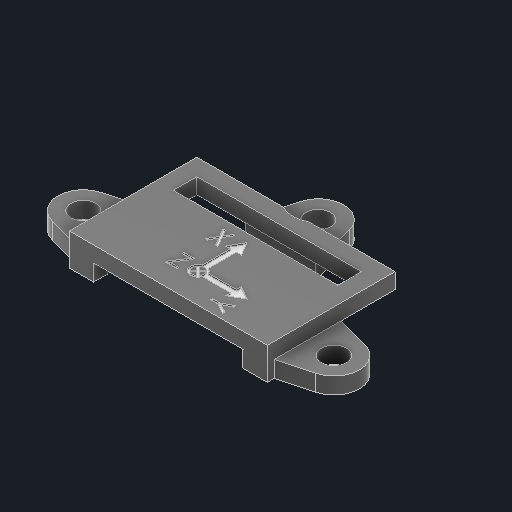
# Autodesk Inventor part: Capa IMU tampa
Saved by Autodesk Inventor 2026.1 (Build 301233000, 233)
## iProperties
Created: 2025-03-19
Part Number: Capa IMU tampa
Material: Genérico
Document SubType Name: Modeling
Designer: Cliente
Density: 1 g/cm^3
Appearance: Padrão
Mass: 3.26729 g
Surface Area: 39.0729 cm^2
Volume: 3.26729 cm^3
Author: Cliente
Autodesk Inventor part; units mm, degrees
ref_plane "YZ Plane" through (0, 0, 0) normal (1, 0, 0) x (0, 1, 0)
ref_plane "XZ Plane" through (0, 0, 0) normal (0, 1, 0) x (-1, 0, 0)
ref_plane "XY Plane" through (0, 0, 0) normal (0, 0, 1) x (1, 0, 0)
sketch "Esboço1" plane through (0, 0, 0) normal (0, 1, 0) x (-1, 0, 0)
  line L0 (-10.5, 6) -> (10.5, 6)
  line L1 (10.5, 6) -> (10.5, -6)
  line L2 (10.5, -6) -> (-10.5, -6)
  line L3 (-10.5, -6) -> (-10.5, 6)
  line L4 (-10.5, 6) -> (10.5, -6) construction
  line L5 (10.5, 6) -> (-10.5, -6) construction
  line L6 (-10.65, -6.15) -> (10.65, -6.15)
  line L7 (10.65, -6.15) -> (10.65, 6.15)
  line L8 (10.65, 6.15) -> (-10.65, 6.15)
  line L9 (-10.65, 6.15) -> (-10.65, -6.15)
  line L10 (12.65, -8.15) -> (-12.65, -8.15)
  line L11 (-12.65, -8.15) -> (-12.65, 8.15)
  line L12 (-12.65, 8.15) -> (12.65, 8.15)
  line L13 (12.65, 8.15) -> (12.65, -8.15)
  circle A0 centre (16, 3) radius 1.6
  circle A1 centre (-16, 3) radius 1.6
  circle A2 centre (0, -11) radius 1.6
  circle A3 centre (0, -11) radius 4 construction
  circle A4 centre (-12.65, -8.15) radius 4 construction
  circle A5 centre (-16, 3) radius 4 construction
  circle A6 centre (-12.65, 8.15) radius 4 construction
  circle A7 centre (12.65, 8.15) radius 4 construction
  circle A8 centre (16, 3) radius 4 construction
  circle A9 centre (12.65, -8.15) radius 4 construction
  line L14 (13.5291, -12.0522) -> (0.8791, -14.9022)
  line L15 (-0.8791, -14.9022) -> (-13.5291, -12.0522)
  line L16 (19.8308, 1.849) -> (16.4808, -9.301)
  line L17 (-16.4808, -9.301) -> (-19.8308, 1.849)
  line L18 (19.353, 5.1811) -> (16.003, 10.3311)
  line L19 (-16.003, 10.3311) -> (-19.353, 5.1811)
  line L20 (12.65, 12.15) -> (-12.65, 12.15)
  arc A10 (13.5291, -12.0522) -> (16.4808, -9.301) centre (12.65, -8.15) ccw
  arc A11 (-0.8791, -14.9022) -> (0.8791, -14.9022) centre (0, -11) ccw
  arc A12 (-16.4808, -9.301) -> (-13.5291, -12.0522) centre (-12.65, -8.15) ccw
  arc A13 (19.8308, 1.849) -> (19.353, 5.1811) centre (16, 3) ccw
  arc A14 (16.003, 10.3311) -> (12.65, 12.15) centre (12.65, 8.15) ccw
  arc A15 (-12.65, 12.15) -> (-16.003, 10.3311) centre (-12.65, 8.15) ccw
  arc A16 (-19.353, 5.1811) -> (-19.8308, 1.849) centre (-16, 3) ccw
  line L21 (10.65, 6.15) -> (5.65, 6.15)
  line L22 (5.65, 6.15) -> (5.65, 3.15)
  line L23 (5.65, 3.15) -> (10.65, 3.15)
  line L24 (10.65, 3.15) -> (10.65, 6.15)
  line L25 (-10.65, 6.15) -> (-8.15, 6.15)
  line L26 (-8.15, 6.15) -> (-8.15, -3.85)
  line L27 (-8.15, -3.85) -> (-10.65, -3.85)
  line L28 (-10.65, -3.85) -> (-10.65, 6.15)
  circle A17 centre (16, 3) radius 3.25
  circle A18 centre (0, -11) radius 3.25
  circle A19 centre (-16, 3) radius 3.25
  line L29 (-16.8412, -0.1393) -> (-12.65, -1.2623)
  line L30 (-16.8412, -0.1393) -> (-12.5022, -0.1393) construction
  line L31 (-16.8412, 6.1393) -> (-12.65, 7.2623)
  line L32 (-16.8412, 6.1393) -> (-12.5022, 6.1393) construction
  line L33 (16.8412, 6.1393) -> (12.65, 7.2623)
  line L34 (16.8412, 6.1393) -> (21.1802, 6.1393) construction
  line L35 (16.8412, -0.1393) -> (12.65, -1.2623)
  line L36 (16.8412, -0.1393) -> (21.1802, -0.1393) construction
  line L37 (-3.1393, -11.8412) -> (-4.1283, -8.15)
  line L38 (-3.1393, -11.8412) -> (0.6821, -11.8412) construction
  line L39 (3.1393, -11.8412) -> (4.1283, -8.15)
  line L40 (3.1393, -11.8412) -> (6.9606, -11.8412) construction
  point P0 (0, 0)
  dimension "d0" = 21
  dimension "d1" = 12
  dimension "d2" = 0.15
  dimension "d3" = 2
  dimension "d4" = 3.2
  dimension "d5" = 3.2
  dimension "d6" = 3.2
  dimension "d7" = 11
  dimension "d8" = 3
  dimension "d9" = 16
  dimension "d10" = 16
  dimension "d11" = 8
  dimension "d12" = 8
  dimension "d13" = 8
  dimension "d14" = 8
  dimension "d15" = 8
  dimension "d16" = 8
  dimension "d17" = 8
  dimension "d22" = 5
  dimension "d23" = 3
  dimension "d24" = 2.5
  dimension "d25" = 10
  dimension "d28" = 6.5
  dimension "d29" = 6.5
  dimension "d33" = 6.5
  dimension "d34" = 15
  dimension "d35" = 15
  dimension "d36" = 165
  dimension "d37" = 165
  dimension "d38" = 105
  dimension "d39" = 75
  constraints: 82 end point, 34 point on circle, 20 centre point, 19 tangent, 17 coincident, 10 horizontal, 10 parallel, 6 equal length, 6 point on line, 5 perpendicular, 2 midpoint, 1 horizontal alignment, 1 vertical alignment, 6 other
  measures "d0" distance of L1.end L2.end
  measures "d1" distance of L0.end L1.end
  measures "d2" distance between parallel lines of L2 L6
  measures "d3" distance between parallel lines of L6 L10
  measures "d4" diameter of A0
  measures "d5" diameter of A1
  measures "d6" diameter of A2
  measures "d7" distance of point (0, 0) A2.centre
  measures "d8" vertical distance of A1.centre point (0, 0)
  measures "d9" horizontal distance of point (0, 0) A1.centre
  measures "d10" horizontal distance of A0.centre point (0, 0)
  measures "d11" diameter of A3
  measures "d12" diameter of A4
  measures "d13" diameter of A5
  measures "d14" diameter of A6
  measures "d15" diameter of A7
  measures "d16" diameter of A8
  measures "d17" diameter of A9
  measures "d22" distance of L23.end L22.end
  measures "d23" distance of L22.end L21.end
  measures "d24" distance of L26.end L27.end
  measures "d25" distance of L25.end L26.end
  measures "d28" diameter of A17
  measures "d29" diameter of A18
  measures "d33" diameter of A19
  measures "d34" angle of L29 L30
  measures "d35" angle of L32 L31
  measures "d36" angle of L34 L33
  measures "d37" angle of L35 L36
  measures "d38" angle of L38 L37
  measures "d39" angle of L40 L39
extrude "Extrusão1" add sketch "Esboço1" against normal blind 2 contours L3 L27 L9 L8 L26 L0 | L0 L26 L27 L3 | L26 L8 L22 L0 | L0 L22 L23 L1 L2 L3 L27 L26 | L3 L2 L1 L23 L7 L6 L9 L27 | L22 L8 L7 L23 L1 L0 | L0 L1 L23 L22 | L10 A18 L11 L12 L13 | L39 A18 L10 | L13 L33 A17 L35 | A18 L10 | L10 A18 | A17 | A18 L37 L10 | L11 L29 A19 L31 | A19 | L14 A11 L15 A12 L17 A16 L19 A15 L20 A14 L18 A13 L16 A10
extrude "Extrusão2" add sketch "Esboço1" along normal blind 3.1 contours L10 A18 L11 L12 L13 | L39 A18 L10 | L13 L33 A17 L35 | A18 L10 | L10 A18 | A17 | A18 L37 L10 | L11 L29 A19 L31 | A19
extrude "Extrusão3" add sketch "Esboço1" along normal blind 1.4 contours L3 L27 L9 L8 L26 L0 | L0 L26 L27 L3 | L22 L8 L7 L23 L1 L0 | L0 L1 L23 L22
sketch "Esboço3" plane through (0, 3.1, 0) normal (0, 1, 0) x (1, 0, 0)
  line L0 (-12.65, -8.15) -> (12.65, -8.15) projected
  line L1 (12.65, -8.15) -> (12.65, -7.2623) projected
  line L2 (12.65, -7.2623) -> (16.8412, -6.1393) projected
  arc A0 (16.8412, -6.1393) -> (16.8412, 0.1393) centre (16, -3) ccw projected
  line L3 (16.8412, 0.1393) -> (12.65, 1.2623) projected
  line L4 (12.65, 1.2623) -> (12.65, 8.15) projected
  line L5 (12.65, 8.15) -> (4.1283, 8.15) projected
  line L6 (4.1283, 8.15) -> (3.1393, 11.8412) projected
  arc A1 (3.1393, 11.8412) -> (-3.1393, 11.8412) centre (0, 11) ccw projected
  line L7 (-3.1393, 11.8412) -> (-4.1283, 8.15) projected
  line L8 (-4.1283, 8.15) -> (-12.65, 8.15) projected
  line L9 (-12.65, 8.15) -> (-12.65, 1.2623) projected
  line L10 (-12.65, 1.2623) -> (-16.8412, 0.1393) projected
  arc A2 (-16.8412, 0.1393) -> (-16.8412, -6.1393) centre (-16, -3) ccw projected
  line L11 (-16.8412, -6.1393) -> (-12.65, -7.2623) projected
  line L12 (-12.65, -7.2623) -> (-12.65, -8.15) projected
  line L13 (10.65, 6.15) -> (10.65, -6.15) projected
  line L14 (10.65, -6.15) -> (-10.65, -6.15) projected
  line L15 (-10.65, -6.15) -> (-10.65, 6.15) projected
  line L16 (-10.65, 6.15) -> (10.65, 6.15) projected
  circle A3 centre (-16, -3) radius 1.6 projected
  circle A4 centre (0, 11) radius 1.6 projected
  circle A5 centre (16, -3) radius 1.6 projected
  line L17 (-12.65, 1.2623) -> (-10.65, 1.7982)
  line L18 (-12.65, -7.2623) -> (-9.337, -8.15)
  line L19 (12.65, -8.15) -> (-12.65, -8.15) projected
  line L20 (-12.65, 1.2623) -> (-16.8412, 0.1393) projected
  line L21 (-16.8412, -6.1393) -> (-12.65, -7.2623) projected
  line L22 (-9.337, -8.15) -> (-9.337, -6.15)
  line L23 (-4.1283, 8.15) -> (-4.6642, 6.15)
  line L24 (10.65, 6.15) -> (-10.65, 6.15) projected
  line L25 (4.1283, 8.15) -> (4.6642, 6.15)
  line L26 (0, 0) -> (0, 2.6223)
  line L27 (4.1283, 8.15) -> (3.1393, 11.8412) projected
  line L28 (-3.1393, 11.8412) -> (-4.1283, 8.15) projected
  line L29 (12.65, 1.2623) -> (10.65, 1.7982)
  line L30 (12.65, -7.2623) -> (9.337, -8.15)
  line L31 (9.337, -8.15) -> (9.337, -6.15)
  constraints: 18 end point, 5 point on line, 4 collinear, 3 symmetric about line, 1 perpendicular, 1 vertical
extrude "Extrusão4" cut sketch "Esboço3" against normal blind 2.1 contours L12 L18 L0 | L18 L11 A2 L10 L17 L15 L14 L22 | L30 L1 L0 | L31 L14 L13 L29 L3 A0 L2 L30 | L23 L7 A1 L6 L25 L16
sketch "Esboço4" plane through (0, 1, 0) normal (0, 1, 0) x (1, 0, 0)
  line L0 (-4.6642, 6.15) -> (-4.1283, 8.15) projected
  line L1 (4.6642, 6.15) -> (-4.6642, 6.15) projected
  line L2 (4.1283, 8.15) -> (4.6642, 6.15) projected
  line L3 (3.1393, 11.8412) -> (4.1283, 8.15) projected
  arc A0 (3.1393, 11.8412) -> (-3.1393, 11.8412) centre (0, 11) ccw projected
  line L4 (-4.1283, 8.15) -> (-3.1393, 11.8412) projected
  circle A1 centre (0, 11) radius 1.6 projected
  line L5 (-12.65, -7.2623) -> (-16.8412, -6.1393) projected
  line L6 (-12.65, -8.15) -> (-12.65, -7.2623) projected
  line L7 (-9.337, -8.15) -> (-12.65, -8.15) projected
  line L8 (-9.337, -6.15) -> (-9.337, -8.15) projected
  line L9 (-10.65, -6.15) -> (-9.337, -6.15) projected
  line L10 (-10.65, -3.15) -> (-10.65, -6.15) projected
  line L11 (-10.65, 1.7982) -> (-10.65, -3.15) projected
  line L12 (-12.65, 1.2623) -> (-10.65, 1.7982) projected
  line L13 (-16.8412, 0.1393) -> (-12.65, 1.2623) projected
  arc A2 (-16.8412, 0.1393) -> (-16.8412, -6.1393) centre (-16, -3) ccw projected
  circle A3 centre (-16, -3) radius 1.6 projected
  line L14 (10.65, 1.7982) -> (12.65, 1.2623) projected
  line L15 (10.65, -6.15) -> (10.65, 1.7982) projected
  line L16 (9.337, -6.15) -> (10.65, -6.15) projected
  line L17 (9.337, -8.15) -> (9.337, -6.15) projected
  line L18 (12.65, -8.15) -> (9.337, -8.15) projected
  line L19 (12.65, -7.2623) -> (12.65, -8.15) projected
  line L20 (16.8412, -6.1393) -> (12.65, -7.2623) projected
  arc A4 (16.8412, -6.1393) -> (16.8412, 0.1393) centre (16, -3) ccw projected
  line L21 (12.65, 1.2623) -> (16.8412, 0.1393) projected
  circle A5 centre (16, -3) radius 1.6 projected
  point P0 (0, 0)
extrude "Extrusão5" add sketch "Esboço4" along normal blind 2.1 separate body
sketch "Esboço5" plane through (0, 3.1, 0) normal (0, 1, 0) x (1, 0, 0)
  line L0 (-4.6642, 6.15) -> (-4.1283, 8.15) projected
  line L1 (-4.1283, 8.15) -> (-12.65, 8.15) projected
  line L2 (-12.65, 8.15) -> (-12.65, 1.2623) projected
  line L3 (-12.65, 1.2623) -> (-10.65, 1.7982) projected
  line L4 (-10.65, 1.7982) -> (-10.65, 6.15) projected
  line L5 (-10.65, 6.15) -> (-4.6642, 6.15) projected
  line L6 (10.65, 1.7982) -> (12.65, 1.2623) projected
  line L7 (12.65, 1.2623) -> (12.65, 8.15) projected
  line L8 (12.65, 8.15) -> (4.1283, 8.15) projected
  line L9 (4.1283, 8.15) -> (4.6642, 6.15) projected
  line L10 (4.6642, 6.15) -> (10.65, 6.15) projected
  line L11 (10.65, 6.15) -> (10.65, 1.7982) projected
  line L12 (9.337, -8.15) -> (9.337, -6.15) projected
  line L13 (9.337, -6.15) -> (-9.337, -6.15) projected
  line L14 (-9.337, -6.15) -> (-9.337, -8.15) projected
  line L15 (-9.337, -8.15) -> (9.337, -8.15) projected
  line L16 (8.15, -6.15) -> (8.15, 3.85) projected
  line L17 (8.15, 3.85) -> (10.65, 3.85) projected
  line L18 (10.65, 3.85) -> (10.65, 6.15) projected
  line L19 (10.65, 6.15) -> (-10.65, 6.15) projected
  line L20 (-10.65, 6.15) -> (-10.65, -3.15) projected
  line L21 (-10.65, -3.15) -> (-5.65, -3.15) projected
  line L22 (-5.65, -3.15) -> (-5.65, -6.15) projected
  line L23 (-5.65, -6.15) -> (8.15, -6.15) projected
  line L24 (-10.65, -6.15) -> (-10.65, -3.15) projected
  line L25 (-9.337, -6.15) -> (-10.65, -6.15) projected
  line L26 (-5.65, -6.15) -> (-9.337, -6.15) projected
  line L27 (-5.65, -6.15) -> (-5.65, -3.15) projected
  line L28 (-5.65, -3.15) -> (-10.65, -3.15) projected
  line L29 (8.15, 3.85) -> (8.15, -6.15) projected
  line L30 (9.337, -6.15) -> (8.15, -6.15) projected
  line L31 (10.65, -6.15) -> (9.337, -6.15) projected
  line L32 (10.65, 1.7982) -> (10.65, -6.15) projected
  line L33 (10.65, 3.85) -> (10.65, 1.7982) projected
  line L34 (10.65, 3.85) -> (8.15, 3.85) projected
  line L35 (10.5, 3) -> (-10.5, 3)
  line L36 (-10.5, 3) -> (-10.5, 6)
  line L37 (-10.5, 6) -> (10.5, 6)
  line L38 (10.5, 6) -> (10.5, 3)
  line L39 (10.5, 3) -> (-10.5, 6) construction
  line L40 (-10.5, 3) -> (10.5, 6) construction
  line L41 (-16.8412, -6.1393) -> (-12.65, -7.2623) projected
  line L42 (-12.65, -7.2623) -> (-12.65, -8.15) projected
  line L43 (-12.65, -8.15) -> (-9.337, -8.15) projected
  line L44 (-9.337, -8.15) -> (-9.337, -6.15) projected
  line L45 (-9.337, -6.15) -> (-10.65, -6.15) projected
  line L46 (-10.65, -6.15) -> (-10.65, 1.7982) projected
  line L47 (-10.65, 1.7982) -> (-16.8412, 0.1393) projected
  arc A0 (-16.8412, 0.1393) -> (-16.8412, -6.1393) centre (-16, -3) ccw projected
  circle A1 centre (-16, -3) radius 1.6 projected
  line L48 (16.8412, 0.1393) -> (10.65, 1.7982) projected
  line L49 (10.65, 1.7982) -> (10.65, -6.15) projected
  line L50 (10.65, -6.15) -> (9.337, -6.15) projected
  line L51 (9.337, -6.15) -> (9.337, -8.15) projected
  line L52 (9.337, -8.15) -> (12.65, -8.15) projected
  line L53 (12.65, -8.15) -> (12.65, -7.2623) projected
  line L54 (12.65, -7.2623) -> (16.8412, -6.1393) projected
  arc A2 (16.8412, -6.1393) -> (16.8412, 0.1393) centre (16, -3) ccw projected
  circle A3 centre (16, -3) radius 1.6 projected
  line L55 (-3.1393, 11.8412) -> (-4.6642, 6.15) projected
  line L56 (-4.6642, 6.15) -> (4.6642, 6.15) projected
  line L57 (4.6642, 6.15) -> (3.1393, 11.8412) projected
  arc A4 (3.1393, 11.8412) -> (-3.1393, 11.8412) centre (0, 11) ccw projected
  circle A5 centre (0, 11) radius 1.6 projected
  circle A6 centre (-16, -3) radius 3.25
  circle A7 centre (16, -3) radius 3.25
  circle A8 centre (0, 11) radius 3.25
  line L58 (-4.1283, 8.15) -> (4.1283, 8.15)
  line L59 (-12.65, 1.2623) -> (-12.65, -7.2623)
  line L60 (12.65, 1.2623) -> (12.65, -7.2623)
  point P0 (0, 0)
  point P1 (0, 4.5)
  point P2 (-1.562, 8.15)
  point P3 (1.562, 8.15)
  dimension "d46" = 21
  dimension "d47" = 3
  dimension "d48" = 0.15
  dimension "d49" = 6.5
  dimension "d50" = 6.5
  dimension "d51" = 6.5
  constraints: 18 end point, 3 centre point, 3 coincident, 3 parallel, 2 horizontal, 2 midpoint, 2 perpendicular, 1 vertical alignment
  measures "d46" distance of L36.end L37.end
  measures "d47" distance of L35.end L36.end
  measures "d48" distance between parallel lines of L5 L37
  measures "d49" diameter of A6
  measures "d50" diameter of A7
  measures "d51" diameter of A8
extrude "Extrusão6" add sketch "Esboço5" along normal blind 2 contours L5 L4 L3 L2 L1 L0 | L19 L10 L11 L17 L38 L37 L36 L35 L16 L13 L22 L21 L20 L4 L5 | L0 L58 A8 L9 L19 | L9 L8 L7 L6 L11 L10 | L20 L24 L25 L14 L43 L42 L59 L3 | L21 L22 L13 L25 L24 | L11 L32 L31 L13 L16 L35 L38 L17 | L60 L53 L52 L12 L31 L32 L6 | L13 L12 L15 L14 bodies 2
sketch "Esboço7" plane through (0, 1, 0) normal (0, 1, 0) x (1, 0, 0)
  line L0 (-12.65, -7.2623) -> (-16.8412, -6.1393) projected
  line L1 (-12.65, -8.15) -> (-12.65, -7.2623) projected
  line L2 (-9.337, -8.15) -> (-12.65, -8.15) projected
  line L3 (-9.337, -6.15) -> (-9.337, -8.15) projected
  line L4 (-10.65, -6.15) -> (-9.337, -6.15) projected
  line L5 (-10.65, -3.15) -> (-10.65, -6.15) projected
  line L6 (-10.65, 1.7982) -> (-10.65, -3.15) projected
  line L7 (-12.65, 1.2623) -> (-10.65, 1.7982) projected
  line L8 (-16.8412, 0.1393) -> (-12.65, 1.2623) projected
  arc A0 (-16.8412, 0.1393) -> (-16.8412, -6.1393) centre (-16, -3) ccw projected
  circle A1 centre (-16, -3) radius 1.6 projected
  line L9 (10.65, 1.7982) -> (12.65, 1.2623) projected
  line L10 (10.65, -6.15) -> (10.65, 1.7982) projected
  line L11 (9.337, -6.15) -> (10.65, -6.15) projected
  line L12 (9.337, -8.15) -> (9.337, -6.15) projected
  line L13 (12.65, -8.15) -> (9.337, -8.15) projected
  line L14 (12.65, -7.2623) -> (12.65, -8.15) projected
  line L15 (16.8412, -6.1393) -> (12.65, -7.2623) projected
  arc A2 (16.8412, -6.1393) -> (16.8412, 0.1393) centre (16, -3) ccw projected
  line L16 (12.65, 1.2623) -> (16.8412, 0.1393) projected
  circle A3 centre (16, -3) radius 1.6 projected
  line L17 (-4.6642, 6.15) -> (-4.1283, 8.15) projected
  line L18 (4.6642, 6.15) -> (-4.6642, 6.15) projected
  line L19 (4.1283, 8.15) -> (4.6642, 6.15) projected
  line L20 (3.1393, 11.8412) -> (4.1283, 8.15) projected
  arc A4 (3.1393, 11.8412) -> (-3.1393, 11.8412) centre (0, 11) ccw projected
  line L21 (-4.1283, 8.15) -> (-3.1393, 11.8412) projected
  circle A5 centre (0, 11) radius 1.6 projected
  line L22 (3.9351, 8.0982) -> (4.4036, 6.35)
  line L23 (4.4036, 6.35) -> (-4.4036, 6.35)
  line L24 (-4.4036, 6.35) -> (-3.9351, 8.0982)
  line L25 (-3.9351, 8.0982) -> (-2.9461, 11.7894)
  arc A6 (2.9461, 11.7894) -> (-2.9461, 11.7894) centre (0, 11) ccw
  line L26 (2.9461, 11.7894) -> (3.9351, 8.0982)
  line L27 (-12.5982, 1.0691) -> (-10.85, 1.5375)
  line L28 (-10.85, 1.5375) -> (-10.85, -3.15)
  line L29 (-10.85, -3.15) -> (-10.85, -6.35)
  line L30 (-10.85, -6.35) -> (-9.537, -6.35)
  line L31 (-9.537, -6.35) -> (-9.537, -7.95)
  line L32 (-9.537, -7.95) -> (-12.45, -7.95)
  line L33 (-12.45, -7.95) -> (-12.45, -7.1088)
  line L34 (-12.45, -7.1088) -> (-16.7894, -5.9461)
  arc A7 (-16.7894, -0.0539) -> (-16.7894, -5.9461) centre (-16, -3) ccw
  line L35 (-16.7894, -0.0539) -> (-12.5982, 1.0691)
  arc A8 (16.7894, -5.9461) -> (16.7894, -0.0539) centre (16, -3) ccw
  line L36 (16.7894, -5.9461) -> (12.45, -7.1088)
  line L37 (12.45, -7.1088) -> (12.45, -7.95)
  line L38 (12.45, -7.95) -> (9.537, -7.95)
  line L39 (9.537, -7.95) -> (9.537, -6.35)
  line L40 (9.537, -6.35) -> (10.85, -6.35)
  line L41 (10.85, -6.35) -> (10.85, 1.5375)
  line L42 (10.85, 1.5375) -> (12.5982, 1.0691)
  line L43 (12.5982, 1.0691) -> (16.7894, -0.0539)
  line L44 (-10.85, 1.5375) -> (-10.65, 1.5911)
  line L45 (-9.537, -7.95) -> (-9.537, -8.15)
  line L46 (-12.65, 1.2623) -> (-12.65, 8.15) projected
  line L47 (-12.65, 1.2623) -> (-12.65, 1.0552)
  line L48 (-4.1283, 8.15) -> (-3.9212, 8.15)
  line L49 (-4.4036, 6.35) -> (-4.4571, 6.15)
  line L50 (-9.537, -6.35) -> (-9.537, -6.1393)
  line L51 (0, 0) -> (0, -2.6962)
  line L52 (10.85, 1.5375) -> (10.65, 1.5911)
  line L53 (9.537, -7.95) -> (9.537, -8.15)
  line L54 (12.65, 1.2623) -> (12.65, 1.0552)
  line L55 (4.1283, 8.15) -> (3.9212, 8.15)
  line L56 (4.4036, 6.35) -> (4.4571, 6.15)
  line L57 (9.537, -6.35) -> (9.537, -6.1393)
  line L58 (-10.65, -3.15) -> (-10.85, -3.15)
  point P0 (-9.537, -6.15)
  point P1 (9.537, -6.15)
  dimension "d55" = 0.2
  dimension "d56" = 0.2
  dimension "d57" = 0.2
  constraints: 72 end point, 6 point on circle, 6 symmetric about line, 5 point on line, 3 centre point, 3 collinear, 2 horizontal, 2 perpendicular, 1 vertical, 22 other
  measures "d55" distance between parallel lines of L20 L26
  measures "d56" distance between parallel lines of L8 L35
  measures "d57" distance between parallel lines of L16 L43
extrude "Extrusão8" cut sketch "Esboço7" along normal blind 2.1 contours L45 L31 L50 L4 L3 L2 | L7 L6 L44 L27 L35 L47 | L9 L54 L43 L42 L52 L10 | L57 L39 L53 L13 L12 L11 | L17 L48 L25 L24 L49 L18 | L56 L22 L26 L55 L19 L18 bodies 2
extrude "Extrusão9" cut sketch "Esboço7" along normal blind 0.6 contours L30 L29 L58 L5 L4 L50 | L52 L41 L40 L57 L11 L10 bodies 2
sketch "Esboço8" plane through (0, 5.1, 0) normal (0, 1, 0) x (1, 0, 0)
  line L0 (-10.5, 6) -> (10.5, 6) projected
  line L1 (-10.5, -6) -> (-10.5, 6) projected
  line L2 (10.5, 6) -> (10.5, -6) projected
  line L3 (10.5, -6) -> (-10.5, -6) projected
  line L4 (10.5, 3) -> (-10.5, 3) projected
  circle A0 centre (0, -4.325) radius 1
  circle A1 centre (0, -4.325) radius 0.75
  line L5 (0.375, -3.325) -> (-0.375, -3.325)
  line L6 (-0.375, -3.325) -> (-0.375, 0.175)
  line L7 (-0.375, 0.175) -> (0.375, 0.175)
  line L8 (0.375, 0.175) -> (0.375, -3.325)
  line L9 (0.375, -3.325) -> (-0.375, 0.175) construction
  line L10 (-0.375, -3.325) -> (0.375, 0.175) construction
  line L11 (-12.65, -8.15) -> (12.65, -8.15) projected
  line L12 (12.65, -8.15) -> (12.65, 8.15) projected
  line L13 (12.65, 8.15) -> (1.562, 8.15) projected
  arc A2 (-1.562, 8.15) -> (1.562, 8.15) centre (0, 11) ccw projected
  line L14 (-1.562, 8.15) -> (-12.65, 8.15) projected
  line L15 (-12.65, 8.15) -> (-12.65, -8.15) projected
  line L16 (10.5, 3) -> (-10.5, 3) projected
  line L17 (-10.5, 3) -> (-10.5, 6) projected
  line L18 (-10.5, 6) -> (10.5, 6) projected
  line L19 (10.5, 6) -> (10.5, 3) projected
  line L20 (1, 0.175) -> (-1, 0.175)
  line L21 (-1, 0.175) -> (0, 1.9071)
  line L22 (0, 1.9071) -> (1, 0.175)
  line L23 (-0.375, -3.325) -> (-0.375, -3.398)
  line L24 (0.375, -3.325) -> (0.375, -3.398)
  line L25 (-0.4419, -4.9437) -> (0.6187, -3.8831)
  line L26 (0.6187, -3.8831) -> (0.4419, -3.7063)
  line L27 (0.4419, -3.7063) -> (-0.6187, -4.7669)
  line L28 (-0.6187, -4.7669) -> (-0.4419, -4.9437)
  line L29 (-0.4419, -4.9437) -> (0.4419, -3.7063) construction
  line L30 (0.6187, -3.8831) -> (-0.6187, -4.7669) construction
  line L31 (-0.4419, -4.9437) -> (1.0581, -4.9437) construction
  line L32 (0.6187, -4.7669) -> (-0.4419, -3.7063)
  line L33 (-0.4419, -3.7063) -> (-0.6187, -3.8831)
  line L34 (-0.6187, -3.8831) -> (0.4419, -4.9437)
  line L35 (0.4419, -4.9437) -> (0.6187, -4.7669)
  line L36 (0.6187, -4.7669) -> (-0.6187, -3.8831) construction
  line L37 (-0.4419, -3.7063) -> (0.4419, -4.9437) construction
  line L38 (0.6187, -4.7669) -> (2.1187, -4.7669) construction
  line L39 (6.2321, -4.325) -> (4.5, -5.325)
  line L40 (4.5, -3.325) -> (6.2321, -4.325)
  line L41 (4.5, -5.325) -> (4.5, -3.325)
  line L42 (1, -3.95) -> (4.5, -3.95)
  line L43 (4.5, -4.7) -> (1, -4.7)
  line L44 (1, -3.95) -> (0.927, -3.95)
  line L45 (1, -4.7) -> (0.927, -4.7)
  line L46 (-3.1, 1.9071) -> (-1.5, 1.9071) construction
  line L47 (-1.5, 1.9071) -> (-1.5, -0.3429) construction
  line L48 (-1.5, -0.3429) -> (-3.1, -0.3429) construction
  line L49 (-3.1, -0.3429) -> (-3.1, 1.9071) construction
  line L50 (6.2321, -5.825) -> (6.2321, -7.425) construction
  line L51 (6.2321, -7.425) -> (3.9821, -7.425) construction
  line L52 (3.9821, -7.425) -> (3.9821, -5.825) construction
  line L53 (3.9821, -5.825) -> (6.2321, -5.825) construction
  line L54 (-3.1, -3.2) -> (-1.5, -3.2) construction
  line L55 (-1.5, -3.2) -> (-1.5, -5.45) construction
  line L56 (-1.5, -5.45) -> (-3.1, -5.45) construction
  line L57 (-3.1, -5.45) -> (-3.1, -3.2) construction
  line L58 (-1.4753, -0.3429) -> (-1.7714, -0.3429)
  line L59 (-1.7714, -0.3429) -> (-2.1314, 0.2967)
  spline S0 degree 2 poles (-2.1314, 0.2967) (-2.265, 0.5311) (-2.3, 0.6113) knots 0 0 0 1 1 1
  line L60 (-2.3, 0.6113) -> (-2.3041, 0.6113)
  spline S1 degree 2 poles (-2.3041, 0.6113) (-2.3041, 0.5826) (-2.8388, -0.3429) knots 0 0 0 1 1 1
  line L61 (-2.8388, -0.3429) -> (-3.1268, -0.3429)
  line L62 (-3.1268, -0.3429) -> (-2.4296, 0.8294)
  line L63 (-2.4296, 0.8294) -> (-3.0466, 1.9071)
  line L64 (-3.0466, 1.9071) -> (-2.7628, 1.9071)
  line L65 (-2.7628, 1.9071) -> (-2.3823, 1.2345)
  spline S2 degree 2 poles (-2.3823, 1.2345) (-2.3206, 1.1255) (-2.2918, 1.0535) knots 0 0 0 1 1 1
  spline S3 degree 2 poles (-2.2918, 1.0535) (-2.2445, 1.1564) (-1.7858, 1.9071) knots 0 0 0 1 1 1
  line L66 (-1.7858, 1.9071) -> (-1.5267, 1.9071)
  line L67 (-1.5267, 1.9071) -> (-2.1581, 0.8479)
  line L68 (-2.1581, 0.8479) -> (-1.4753, -0.3429)
  line L69 (6.2321, -7.4497) -> (4.9363, -6.7319)
  line L70 (4.9363, -6.7319) -> (3.9821, -6.7319)
  line L71 (3.9821, -6.7319) -> (3.9821, -6.4913)
  line L72 (3.9821, -6.4913) -> (4.9363, -6.4913)
  line L73 (4.9363, -6.4913) -> (6.2321, -5.7982)
  line L74 (6.2321, -5.7982) -> (6.2321, -6.0882)
  line L75 (6.2321, -6.0882) -> (5.4752, -6.4831)
  spline S4 degree 2 poles (5.4752, -6.4831) (5.36, -6.5427) (5.1729, -6.625) knots 0 0 0 1 1 1
  spline S5 degree 2 poles (5.1729, -6.625) (5.3004, -6.6785) (6.2321, -7.1721) knots 0 0 0 1 1 1
  line L76 (6.2321, -7.1721) -> (6.2321, -7.4497)
  line L77 (-1.5997, -5.45) -> (-3.0229, -5.45)
  line L78 (-3.0229, -5.45) -> (-3.0229, -5.1703)
  line L79 (-3.0229, -5.1703) -> (-2.0995, -3.7327)
  spline S6 degree 2 poles (-2.0995, -3.7327) (-2.0995, -3.7286) (-1.9699, -3.5373) (-1.9144, -3.4653) knots 0 0 0 1 2 2 2
  line L80 (-1.9144, -3.4653) -> (-2.9201, -3.4653)
  line L81 (-2.9201, -3.4653) -> (-2.9201, -3.2)
  line L82 (-2.9201, -3.2) -> (-1.6306, -3.2)
  line L83 (-1.6306, -3.2) -> (-1.6306, -3.4653)
  line L84 (-1.6306, -3.4653) -> (-2.6404, -5.0222)
  line L85 (-2.6404, -5.0222) -> (-2.7494, -5.1826)
  line L86 (-2.7494, -5.1826) -> (-1.5997, -5.1826)
  line L87 (-1.5997, -5.1826) -> (-1.5997, -5.45)
  point P0 (0, 0)
  point P1 (0, -1.575)
  point P2 (0, 0.7524)
  point P3 (0, 0.175)
  point P4 (4.5, -4.325)
  point P5 (-0.6113, -4.7595)
  point P6 (-0.6113, -3.8905)
  point P7 (-0.1768, -4.325)
  point P8 (0.6113, -3.8905)
  point P9 (0.6113, -4.7595)
  point P10 (0.1768, -4.325)
  point P11 (-0.375, 0.175)
  point P12 (-0.4345, -4.9363)
  point P13 (0, -4.5018)
  point P14 (0.4345, -4.9363)
  point P15 (0.4345, -3.7137)
  point P16 (0, -4.1482)
  point P17 (-0.4345, -3.7137)
  point P18 (4.5, -4.325)
  point P19 (0, -4.325)
  point P20 (-1.5, -4.325)
  point P21 (0, -4.325)
  dimension "d62" = 2
  dimension "d63" = 1.5
  dimension "d64" = 0.75
  dimension "d65" = 3.5
  dimension "d67" = 3.825
  dimension "d68" = 2
  dimension "d69" = 45
  dimension "d70" = 0.25
  dimension "d71" = 135
  dimension "d72" = 0.25
  dimension "d75" = 270
  dimension "d79" = 2.25
  dimension "d80" = 1.6
  dimension "d82" = 2.25
  dimension "d83" = 1.6
  dimension "d85" = 1.5
  dimension "d86" = 1.5
  dimension "d87" = 2.25
  dimension "d88" = 1.6
  dimension "d89" = 1.5
  constraints: 64 end point, 12 midpoint, 7 parallel, 5 horizontal, 3 perpendicular, 3 tangent, 3 vertical alignment, 2 centre point, 2 equal length, 2 horizontal alignment, 2 point on circle, 1 coincident, 1 vertical, 31 other
  measures "d62" diameter of A0
  measures "d63" diameter of A1
  measures "d64" distance of L6.end L7.end
  measures "d65" distance of L5.end L6.end
  measures "d67" distance from line of L11 A0.centre
  measures "d68" distance of L20.start L20.end
  measures "d69" angle of L31 L25
  measures "d70" distance of L26.end L25.end
  measures "d71" angle of L38 L32
  measures "d72" distance of L33.end L32.end
  measures "d79" distance of L48.end L46.start
  measures "d80" distance of L46.start L46.end
  measures "d82" distance of L52.end L50.start
  measures "d83" distance of L50.start L50.end
  measures "d85" distance from line of L55 point (0, -4.325)
  measures "d86" distance from line of L47 point (0, 0.175)
  measures "d87" distance of L56.end L54.start
  measures "d88" distance of L54.start L54.end
  measures "d89" distance from line of L53 point (4.5, -4.325)
extrude "Extrusão10" cut sketch "Esboço8" against normal blind 0.2 contours L73 L74 L3 | L3 L74 L75 S4 S5 L76 L69 L70 L71 L72 L73 | A0 | A0 L44 L42 L41 L43 L45 | A0 L5 L24 | L23 L5 A0 | L5 L6 L7 L8 | L41 L40 L39 | L7 L20 L21 L22 | L25 L32 L27 A1 | A1 L26 L25 | L32 L35 A1 | A1 L34 L25 L32 | A1 L27 L26 | L25 L34 L27 L32 | L35 L34 A1 | L25 A1 L27 L34 | L27 L34 A1 L32 | A1 L33 L32 | L25 L28 A1 | A1 L34 L33 | L28 L27 A1 | L58 L59 S0 L60 S1 L61 L62 L63 L64 L65 S2 S3 L66 L67 L68 | L77 L78 L79 S6 L80 L81 L82 L83 L84 L85 L86 L87 bodies 2
